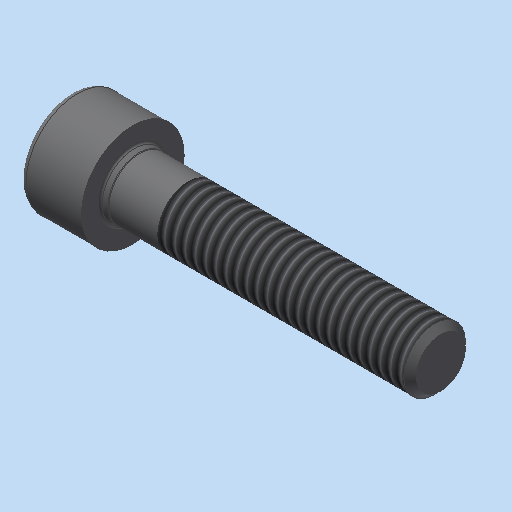
# Autodesk Inventor part: Zylinderschraube_ISO_4762___M6x30
Saved by Autodesk Inventor 2023.3 (Build 273359000, 359)
## iProperties
Shininess: 64.0
Length Units: 11269
Angle Units: 11279
Time Units: 11290
Mass Units: 11283
Length Display Precision: 3
Angle Display Precision: 2
Compacted: True
Part Number: Zylinderschraube_ISO_4762___M6x30
Document SubType Name: Modeling
Created: 2004-04-03
Material: xStahl_AnP_Dummymaterial
Description: =<RBPARTNOTITLE2>
Vendor: NORM8
Designer: S.Riedelsheimer
Manufacturer: Standard
Standards Organization: Custom
Density: 7.85 g/cm^3
Appearance: Stahl - normal AnP
Mass: 9.61751 g
Surface Area: 9.563 cm^2
Volume: 1.22516 cm^3
DOC_ID: 5 F45 Zylinderschraube_ISO_4762___M6x30
GAIN_REFID: 20__Zylinderschraube_ISO_4762___M6x30:A931D
Control State: 0
Master: False
Checked Out: False
CNS_NB: Zylinderschraube ISO 4762 - M6x30
CNS_NN: ISO 4762
CNS_NT: Zylinderschrauben mit Innensechskant
CNS_NBSYN: Zylinderschraube ISO 4762 - $NENN.
CNS_LINA: Zylinderschraube ISO 4762 - M6x30
CNS_D: 6.000
CNS_D3: 4.773
CNS_P: 1.000
CNS_L: 30.000
CNS_S: 5.000
CNS_HM: 24.000
CNS_DK: 10.000
CNS_DA: 6.800
CNS_DS: 6.000
CNS_E: 5.720
CNS_K: 6.000
CNS_R: 0.250
CNS_T: 3.000
CNS_V: 0.600
CNS_DW: 9.380
CNS_W: 2.300
CNS_LF: 0.680
CNS_LG: 3.000
CNS_FORM: 0.000
CNS_NENN: M6x30
CNS_KT: DUMMY
PSOL_IDENT_0: {C:\partsolutions8\data\23d-libs\bosch_bamberg\schrauben\zylinderschrauben\din_en_iso_4762.prj},170
PSOL_IDENT_1: {M=Nenngewinde},{VTYP=3D},{NB=Zylinderschraube ISO 4762 - M6x30},{NN=ISO 4762},{DATE=26.11.2003},{GE
PSOL_IDENT_2: OMDATE=26.11.2003},{VERSION=v2},{LINEID=630},{LINESUBID=-1},{WBVAR=}  {NB=Zylinderschraube ISO 4762
PSOL_IDENT_3: - M6x30},{LINA=Zylinderschraube ISO 4762 - M6x30},{KT=DUMMY},{IDNR=},{D=6.000},{D3=4.773},{P=1.000},
PSOL_IDENT_4: {L=30.000},{S=5.000},{HM=24.000},{DK=10.000},{DA=6.800},{DS=6.000},{E=5.720},{K=6.000},{R=0.250},{T=
PSOL_IDENT_5: 3.000},{V=0.600},{DW=9.380},{W=2.300},{LF=0.680},{LG=3.000},{FORM=0.000},{NENN=M6x30}
Masse: 0,001 kg
Volumen: 1225,161 mm^3
Fläche: 956,300 mm^2
DEF_STKID: T18313
Bezeichnung1: Zylinderschraube ISO 4762 - M6x30
Bezeichnung2: Zylinderschrauben mit Innensechskant
RBPARTNOTITLE2: Zylinderschrauben mit Innensechskant
RBPARTNOTITLE1: Hexagon socket head cap screws
AnP_Kategorie: 4
RBDRAWINGMISSINGSPEC: --
RBPARTMADEOF: ISO 4762 - M6x30 - 8.8 verzinkt
Density: 0.0
Volumn: 0.0
Area: 0.0
PropertySet Name: Model Information
Title: Zylinderschraube ISO 4762 - M6x30
Author: S.Riedelsheimer
Keywords: =<RBPARTMADEOF>
Comments: =<RBSURFACE2>
Revision Number: 01
Autodesk Inventor part; units mm, degrees
sketch "Sketch_1" plane through (0, 0, 0) normal (0, 1, 0) x (-1, 0, 0)
  line L0 (-33, 0) -> (9, 0)
  line L1 (0.8566, 0) -> (2.3, -2.5)
  line L2 (2.3, -2.5) -> (5.64, -2.5)
  line L3 (5.64, -2.5) -> (6, -2.86)
  line L4 (6, -2.86) -> (6, -4.4)
  arc A0 (5.4, -5) -> (6, -4.4) centre (5.4, -4.4) ccw
  line L5 (5.4, -5) -> (0, -5)
  line L6 (0, -5) -> (0, -3.4)
  arc A1 (0, -3.4) -> (-0.1677, -3.1639) centre (-0.25, -3.4) ccw
  line L7 (-0.1677, -3.1639) -> (-0.5977, -3.0139)
  arc A2 (-0.5977, -3.0139) -> (-0.68, -3) centre (-0.68, -3.25) ccw
  line L8 (-0.68, -3) -> (-29.3865, -3)
  line L9 (-29.3865, -3) -> (-30, -2.3865)
  line L10 (-30, -2.3865) -> (-30, 0)
  line L11 (-30, 0) -> (0.8566, 0)
  constraints: 24 end point, 6 point on circle, 3 centre point
revolve "Drehung1" add sketch "Sketch_1" angle 360 about axis through (33, 0, 0) along (1, 0, 0)
thread "Gewinde1" size "M6x1" class "6g" standard "ANSI Metric M Profile" length 24
sketch "Skizze_1" plane through (-2.3, 0, 0) normal (1, 0, 0) x (0, 0, -1)
  line L0 (-2.5, 1.4434) -> (-2.5, -1.4434)
  line L1 (-2.5, -1.4434) -> (0, -2.8868)
  line L2 (0, -2.8868) -> (2.5, -1.4434)
  line L3 (2.5, -1.4434) -> (2.5, 1.4434)
  line L4 (2.5, 1.4434) -> (0, 2.8868)
  line L5 (0, 2.8868) -> (-2.5, 1.4434)
  constraints: 12 end point
extrude "Extrusion1" cut sketch "Skizze_1" against normal blind 6
ref_plane "IP1_XY" through (0, 0, 0) normal (1, 0, 0) x (0, 0, -1)
ref_plane "IP1_YZ" through (0, 0, 0) normal (0, 0, -1) x (0, 1, 0)
ref_plane "IP3_XY" through (30, 0, 0) normal (1, 0, 0) x (0, 0, -1)
ref_plane "IP3_YZ" through (30, 0, 0) normal (0, 0, -1) x (0, 1, 0)
ref_plane "IP2_XY" through (-6, 0, 0) normal (1, 0, 0) x (0, 0, -1)
ref_plane "IP2_YZ" through (-6, 0, 0) normal (0, 0, -1) x (0, 1, 0)
